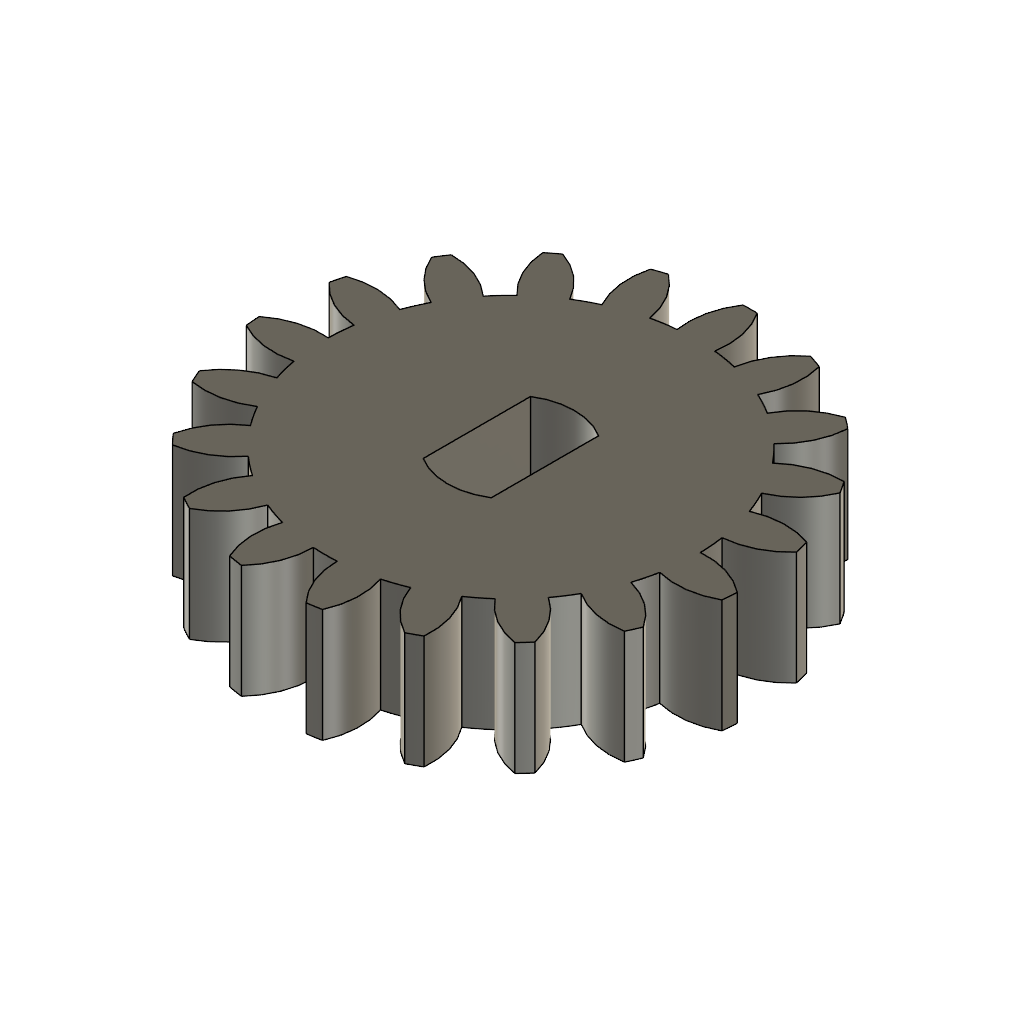
Pignon (Autodesk Fusion 360 design; units mm, degrees)
Autodesk Fusion 360 part; units mm, degrees
sketch "Esquisse1" plane through (0, 0, 0) normal (0, 0, 1) x (1, 0, 0)
  circle A0 centre (0, 0) radius 8.2
  dimension "d1" = 16.4
  measures "d1" diameter of A0
extrude "Extrusion1" add sketch "Esquisse1" along normal blind 5
sketch "Esquisse2" plane through (0, 0, 0) normal (0, 0, 1) x (1, 0, 0)
  arc A0 (0.3144, 10.5454) -> (-0.3146, 10.5454) centre (-0.0001, 0.0001) ccw
  arc A1 (0.7689, 7.8625) -> (-0.7691, 7.8625) centre (-0.0001, 0) ccw
  arc A2 (0.7689, 7.8625) -> (0.3144, 10.5454) centre (-2.455, 8.6963) ccw
  arc A3 (-0.3146, 10.5454) -> (-0.7691, 7.8625) centre (2.4548, 8.6962) ccw
  dimension "d4" = 21.1
  dimension "d5" = 15.8
  dimension "d6" = 3.33
  dimension "d7" = 0.629
  dimension "d8" = 1.538
  constraint coincident A0.start A2.end
  constraint coincident A1.start A2.start
  constraint coincident A0.end A3.start
  constraint coincident A1.end A3.end
  constraint horizontal A0.start A0.end
  constraint horizontal A1.start A1.end
  constraint equal A2 A3
  measures "d4" diameter of A0
  measures "d5" diameter of A1
  measures "d6" radius of A2
  measures "d7" horizontal distance of A0.start A0.end
  measures "d8" horizontal distance of A1.start A1.end
extrude "Extrusion2" add sketch "Esquisse2" along normal blind 5
pattern_circular "Réseau C1" count 19 over 360 about axis through (0, 0, 1.75) along (0, 0, 1) of "Extrusion2"
sketch "Esquisse3" plane through (0, 0, 0) normal (0, 0, 1) x (1, 0, 0)
  arc A0 (1.5, 2.3643) -> (-1.5, 2.3643) centre (0, 0) ccw
  arc A1 (-1.5, -2.3643) -> (1.5, -2.3643) centre (0, 0) ccw
  line L0 (1.5, -2.3643) -> (1.5, 2.3643)
  line L1 (-1.5, 2.3643) -> (-1.5, -2.3643)
  dimension "d13" = 5.6
  dimension "d14" = 3
  constraint vertical L0
  constraint vertical L1
  constraint horizontal A0.start A0.end
  constraint equal A0 A1
  measures "d13" diameter of A0
  measures "d14" horizontal distance of A0.start A0.end
extrude "Extrusion3" cut sketch "Esquisse3" along normal through all
